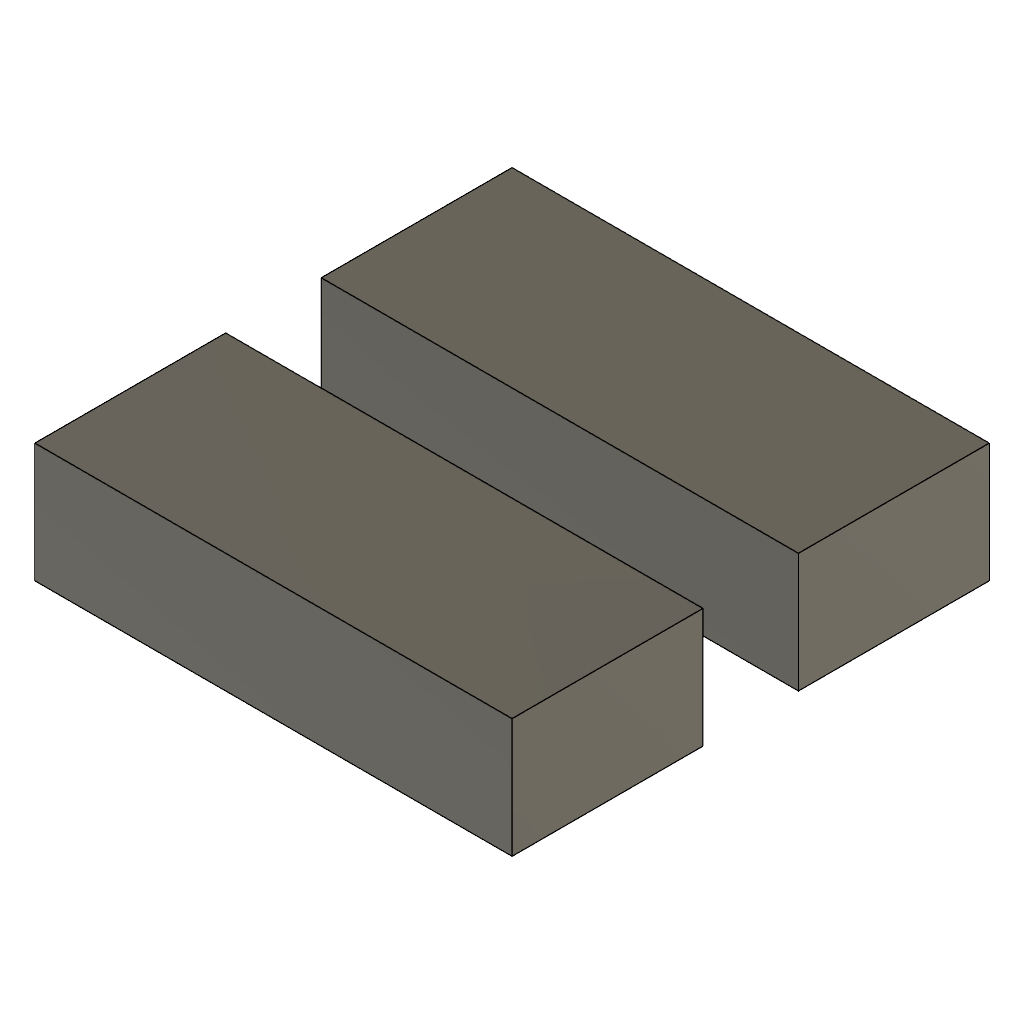
combine_cut_split (Autodesk Fusion 360 design; units mm, degrees)
Autodesk Fusion 360 part; units mm, degrees
sketch "Sketch1" plane through (0, 0, 0) normal (0, 0, 1) x (1, 0, 0)
  line L0 (-20, -20) -> (20, -20)
  line L1 (20, -20) -> (20, 20)
  line L2 (20, 20) -> (-20, 20)
  line L3 (-20, 20) -> (-20, -20)
extrude "Extrude1" add sketch "Sketch1" along normal blind 10 makes body 1
ref_plane "WorkPlane1" through (0, 0, -1) normal (0, 0, 1) x (1, 0, 0)
sketch "Sketch2" plane through (0, 0, -1) normal (0, 0, 1) x (1, 0, 0)
  line L0 (-30, -4) -> (30, -4)
  line L1 (30, -4) -> (30, 4)
  line L2 (30, 4) -> (-30, 4)
  line L3 (-30, 4) -> (-30, -4)
extrude "Extrude2" add sketch "Sketch2" along normal blind 12 separate body makes body 2
combine "Combine1" operation cut target body 1 tool bodies 2 makes body 3 at (-6.6667, -9.3333, 0)
named bodies: "Bar", "T (1)"
